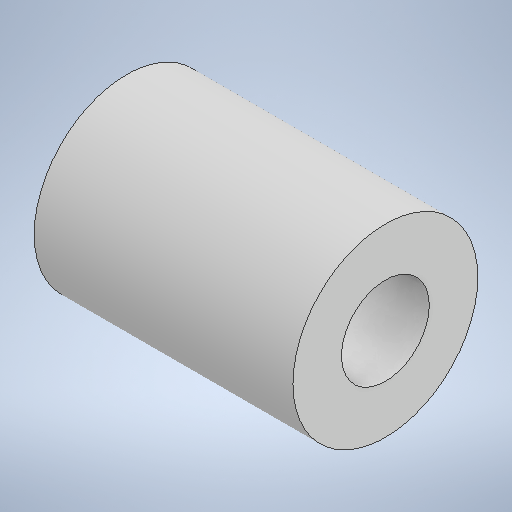
# Autodesk Inventor part: cilindro_ext_pasante
Saved by Autodesk Inventor 2025.2 (Build 292293000, 293)
## iProperties
Created: 2025-03-19
Part Number: cilindro_ext_pasante
Material: Generic
Document SubType Name: Modeling
Designer: laura
Density: 1 g/cm^3
Appearance: Default
Author: laura
Autodesk Inventor part; units mm, degrees
ref_plane "YZ Plane" through (0, 0, 0) normal (1, 0, 0) x (0, 1, 0)
ref_plane "XZ Plane" through (0, 0, 0) normal (0, 1, 0) x (-1, 0, 0)
ref_plane "XY Plane" through (0, 0, 0) normal (0, 0, 1) x (1, 0, 0)
sketch "Sketch1" plane through (0, 0, 0) normal (0, 1, 0) x (-1, 0, 0)
  line L0 (14, 0) -> (-14, 0)
  line L1 (14, -10) -> (-14, -10)
  line L2 (14, -4.75) -> (-14, -4.75)
  line L3 (-14, -4.75) -> (-14, -10)
  line L4 (14, -10) -> (14, -4.75)
  line L5 (-14, -4.75) -> (-14, 0) construction
  line L6 (14, -4.75) -> (14, 0) construction
  point P0 (0, 0)
  point P1 (0, 0)
  dimension "d0" = 20
  dimension "d1" = 9.5
  dimension "d2" = 28
  constraints: 14 end point, 2 horizontal, 2 perpendicular, 2 vertical, 1 coincident, 1 midpoint
  measures "d0" diameter of L1 L0
  measures "d1" diameter of L2 L0
  measures "d2" distance between parallel lines of L3 L4
revolve "Revolution1" add sketch "Sketch1" angle 360 about axis through (-14, 0, 0) along (1, 0, 0)
body "Solid1"
